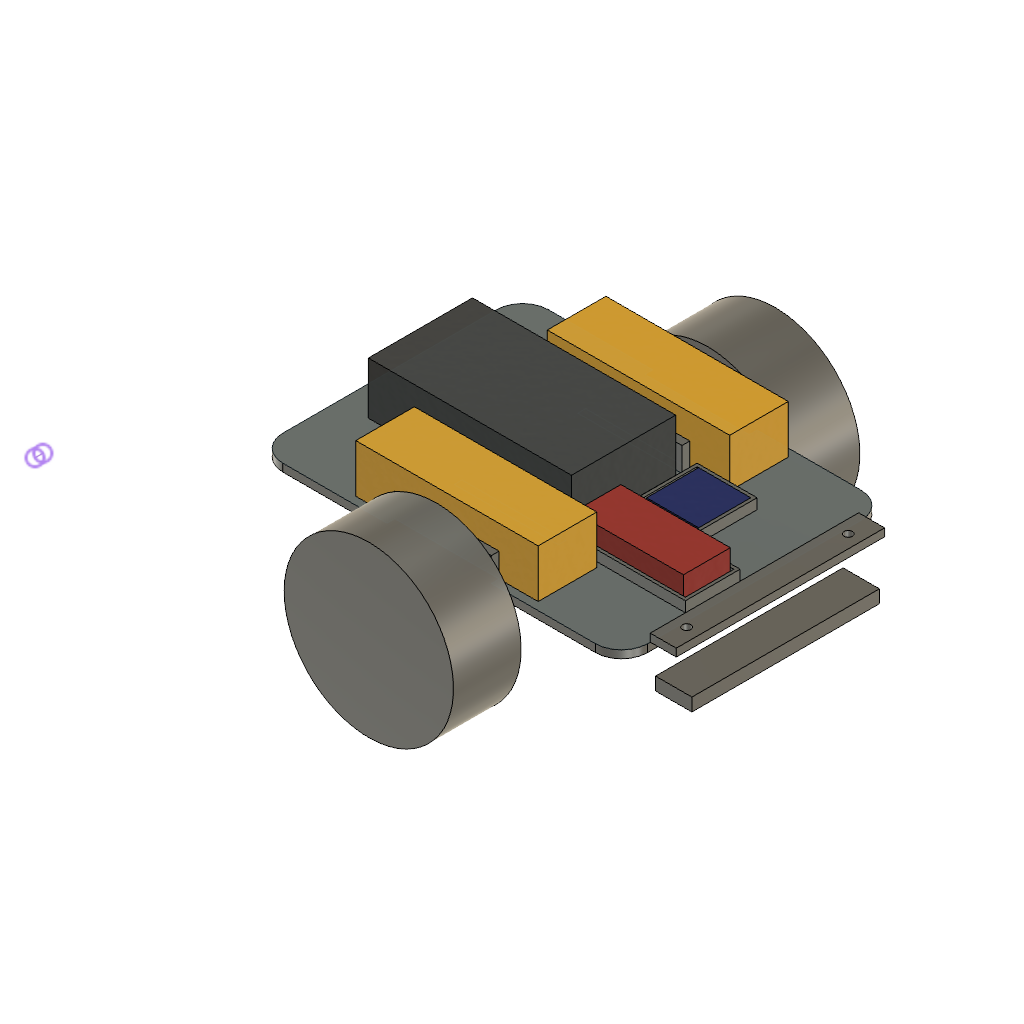
chassis_v1 (Autodesk Fusion 360 design; units mm, degrees)
part number: 2026-11-08-02-27-47-931
part number: 2026-11-08-02-40-19-347
part number: 2026-11-08-02-51-22-051
part number: 2026-11-08-02-55-13-605
part number: 2026-11-08-03-02-01-941
part number: 2026-11-08-03-06-04-735
part number: 2026-11-08-03-13-26-810
part number: 2026-11-08-10-06-36-840
part number: 2026-11-09-11-55-17-820
part number: 2026-11-09-12-28-01-663
Autodesk Fusion 360 part; units mm, degrees
form "Form1" [no effect] in component "DUMMY_Motor"
sketch "sketch 289" plane through (0, 0, 0) normal (0, 0, 1) x (1, 0, 0)
  line L0 (0, 0) -> (70, 0)
  line L1 (70, 0) -> (70, -22.5)
  line L2 (70, -22.5) -> (0, -22.5)
  line L3 (0, -22.5) -> (0, 0)
  constraint horizontal L0
  constraint vertical L1
  constraint horizontal L2
  constraint vertical L3
  constraint coincident L0.start L3.end
extrude "Extrude1" add sketch "sketch 289" along normal blind 18.5 makes body 1 in component "DUMMY_Motor"
form "Form1'" [no effect] in component "DUMMY_Nano"
sketch "sketch 438" plane through (0, 0, 0) normal (0, 0, 1) x (1, 0, 0)
  line L0 (0, 0) -> (42, 0)
  line L1 (42, 0) -> (42, -18)
  line L2 (42, -18) -> (0, -18)
  line L3 (0, -18) -> (0, 0)
  constraint horizontal L0
  constraint vertical L1
  constraint horizontal L2
  constraint vertical L3
  constraint coincident L0.start L3.end
extrude "Extrude1'" add sketch "sketch 438" along normal blind 8 separate body makes body 2 in component "DUMMY_Nano"
form "Form1''" [no effect] in component "DUMMY_Driver"
sketch "sketch 581" plane through (0, 0, 0) normal (0, 0, 1) x (1, 0, 0)
  line L0 (0, 0) -> (20, 0)
  line L1 (20, 0) -> (20, -20)
  line L2 (20, -20) -> (0, -20)
  line L3 (0, -20) -> (0, 0)
  constraint horizontal L0
  constraint vertical L1
  constraint horizontal L2
  constraint vertical L3
  constraint coincident L0.start L3.end
extrude "Extrude1''" add sketch "sketch 581" along normal blind 4 separate body makes body 3 in component "DUMMY_Driver"
move_face "MoveFace1" by (0, -60, 0) 1 faces at (6.6667, -6.6667, 4) on bodies 3 in component "DUMMY_Driver"
sketch "Sketch1" plane through (0, 0, 0) normal (0, 0, 1) x (1, 0, 0) in component "DUMMU_Wheel"
  circle A0 centre (0, 0) radius 32.5
  dimension "d25" = 65
  constraint coincident A0.centre origin
  measures "d25" diameter of A0
extrude "Extrude1'''" add sketch "Sketch1" along normal blind 26 separate body makes body 4 in component "DUMMU_Wheel"
sketch "Sketch1 (2)" plane through (0, 0, 0) normal (0, 0, 1) x (1, 0, 0) in component "Dummy_caster"
  circle A0 centre (0, 0) radius 7.5
  dimension "d28" = 15
  constraint coincident A0.centre origin
  measures "d28" diameter of A0
extrude "Extrude1''''" add sketch "Sketch1 (2)" along normal blind 20.25 separate body makes body 5 in component "Dummy_caster"
sketch "Sketch1 (3)" plane through (0, 0, 0) normal (0, 1, 0) x (1, 0, 0) in component "DUMMY_BATTERY"
sketch "Sketch2" plane through (0, 0, 0) normal (0, 0, 1) x (1, 0, 0) in component "DUMMY_BATTERY"
  line L0 (0, 0) -> (78, 0)
  line L1 (78, 0) -> (78, -40)
  line L2 (78, -40) -> (0, -40)
  line L3 (0, -40) -> (0, 0)
  dimension "d31" = 78
  dimension "d32" = 40
  constraint horizontal L0
  constraint vertical L1
  constraint horizontal L2
  constraint vertical L3
  constraint coincident L0.start L3.end
  measures "d31" distance of L0.start L0.end
  measures "d32" distance of L0.start L2.end
extrude "Extrude1'''''" add sketch "Sketch2" along normal blind 20 separate body makes body 6 in component "DUMMY_BATTERY"
sketch "Sketch1 (4)" plane through (0, 0, 0) normal (0, 0, 1) x (1, 0, 0) in component "Chassis"
  line L0 (0, 0) -> (140, 0)
  line L1 (140, 0) -> (140, 102)
  line L2 (140, 102) -> (0, 102)
  line L3 (0, 102) -> (0, 0)
  dimension "d40" = 140
  dimension "d41" = 102
  constraint horizontal L0
  constraint vertical L1
  constraint horizontal L2
  constraint vertical L3
  constraint coincident L0.start L3.end
  measures "d40" distance of L0.start L0.end
  measures "d41" distance of L0.start L2.end
extrude "Extrude1''''''" add sketch "Sketch1 (4)" along normal blind 3 separate body makes body 7 in component "Chassis"
fillet "Fillet1" radius 10 4 edges at (140, 0, 1.5) (140, 102, 1.5) (0, 102, 1.5) (0, 0, 1.5) on bodies 7 in component "Chassis"
sketch "Sketch2 (2)" plane through (0, 0, 3) normal (0, 0, 1) x (-1, 0, 0) in component "Chassis"
  arc A0 (0, -10) -> (-10, 0) centre (-10, -10) ccw
  line L0 (-10, 0) -> (-130, 0)
  arc A1 (-130, 0) -> (-140, -10) centre (-130, -10) ccw
  line L1 (-140, -10) -> (-140, -92)
  arc A2 (-140, -92) -> (-130, -102) centre (-130, -92) ccw
  line L2 (-130, -102) -> (-10, -102)
  arc A3 (-10, -102) -> (0, -92) centre (-10, -92) ccw
  line L3 (0, -92) -> (0, -10)
  line L4 (-50, 0) -> (-90, 0)
  line L5 (-90, 0) -> (-90, -3)
  line L6 (-90, -3) -> (-50, -3)
  line L7 (-50, -3) -> (-50, 0)
  line L8 (-50, -28.8) -> (-90, -28.8)
  line L9 (-90, -28.8) -> (-90, -25.8)
  line L10 (-90, -25.8) -> (-50, -25.8)
  line L11 (-50, -25.8) -> (-50, -28.8)
  dimension "d53" = 40
  dimension "d54" = 3
  dimension "d55" = 40
  dimension "d56" = 3
  dimension "d57" = 25.8
  dimension "d58" = 50
  dimension "d59" = 50
  constraint horizontal L4
  constraint vertical L5
  constraint horizontal L6
  constraint vertical L7
  constraint coincident L0 L4.start
  constraint horizontal L8
  constraint vertical L9
  constraint horizontal L10
  constraint vertical L11
  measures "d53" distance of L4.start L4.end
  measures "d54" distance of L4.start L6.end
  measures "d55" distance of L8.start L8.end
  measures "d56" distance of L8.start L10.end
  measures "d57" distance of L0 L10
  measures "d58" distance of L3 L11
  measures "d59" distance of L3 L7
sketch "Sketch3" plane through (0, 0, 3) normal (0, 0, 1) x (-1, 0, 0) in component "Chassis"
  line L0 (39.3103, 42.7588) -> (-0.6897, 42.7588)
  line L1 (-0.6897, 42.7588) -> (-0.6897, 45.7588)
  line L2 (-0.6897, 45.7588) -> (39.3103, 45.7588)
  line L3 (39.3103, 45.7588) -> (39.3103, 42.7588)
  dimension "d48" = 40
  dimension "d49" = 3
  constraint horizontal L0
  constraint vertical L1
  constraint horizontal L2
  constraint vertical L3
  measures "d48" distance of L0.start L0.end
  measures "d49" distance of L0.start L2.end
sketch "Sketch4" plane through (0, 0, 3) normal (0, 0, 1) x (-1, 0, 0) in component "Chassis"
  line L0 (-54.873, 44.0948) -> (-94.873, 44.0948)
  line L1 (-94.873, 44.0948) -> (-94.873, 47.0948)
  line L2 (-94.873, 47.0948) -> (-54.873, 47.0948)
  line L3 (-54.873, 47.0948) -> (-54.873, 44.0948)
  dimension "d50" = 40
  dimension "d51" = 3
  constraint horizontal L0
  constraint vertical L1
  constraint horizontal L2
  constraint vertical L3
  measures "d50" distance of L0.start L0.end
  measures "d51" distance of L0.start L2.end
sketch "Sketch5" plane through (0, 0, 3) normal (0, 0, 1) x (-1, 0, 0) in component "Chassis"
sketch "Sketch6" plane through (0, 0, 3) normal (0, 0, 1) x (-1, 0, 0) in component "Chassis"
  line L0 (39.3103, 45.7588) -> (39.3103, 42.7588)
sketch "Sketch7" plane through (0, 0, 3) normal (0, 0, 1) x (1, 0, 0) in component "Chassis"
sketch "Sketch8" plane through (0, 0, 3) normal (0, 0, 1) x (-1, 0, 0) in component "Chassis"
sketch "Sketch9" plane through (0, 0, 3) normal (0, 0, 1) x (-1, 0, 0) in component "Chassis"
sketch "Sketch10" plane through (0, 0, 3) normal (0, 0, 1) x (-1, 0, 0) in component "Chassis"
sketch "Sketch11" plane through (0, 0, 3) normal (0, 0, 1) x (-1, 0, 0) in component "Chassis"
extrude "Extrude2" add sketch "Sketch2 (2)" along normal blind 9.25 contours L0 L4 L5 L6 L7 | L8 L9 L10 L11 bodies 7 in component "Chassis"
ref_plane "WorkPlane1" through (70, 51, 6.125) normal (0, -1, 0) x (1, 0, 0) in component "Chassis"
mirror "Mirror1" about plane through (70, 51, 6.125) normal (0, -1, 0) of "Extrude2" in component "Chassis"
sketch "Sketch12" plane through (0, 0, 3) normal (0, 0, 1) x (-1, 0, 0) in component "Chassis"
  line L0 (-50, -99) -> (-50, -102)
  line L1 (-50, -102) -> (-10, -102)
  arc A0 (-10, -102) -> (0, -92) centre (-10, -92) ccw
  line L2 (0, -92) -> (0, -10)
  arc A1 (0, -10) -> (-10, 0) centre (-10, -10) ccw
  line L3 (-10, 0) -> (-50, 0)
  line L4 (-50, 0) -> (-50, -3)
  line L5 (-50, -3) -> (-90, -3)
  line L6 (-90, -3) -> (-90, 0)
  line L7 (-90, 0) -> (-130, 0)
  arc A2 (-130, 0) -> (-140, -10) centre (-130, -10) ccw
  line L8 (-140, -10) -> (-140, -92)
  arc A3 (-140, -92) -> (-130, -102) centre (-130, -92) ccw
  line L9 (-130, -102) -> (-90, -102)
  line L10 (-90, -102) -> (-90, -99)
  line L11 (-90, -99) -> (-50, -99)
  line L12 (-50, -73.2) -> (-50, -76.2)
  line L13 (-50, -76.2) -> (-90, -76.2)
  line L14 (-90, -76.2) -> (-90, -73.2)
  line L15 (-90, -73.2) -> (-50, -73.2)
  line L16 (-50, -25.8) -> (-50, -28.8)
  line L17 (-50, -28.8) -> (-90, -28.8)
  line L18 (-90, -28.8) -> (-90, -25.8)
  line L19 (-90, -25.8) -> (-50, -25.8)
mirror "Mirror1'" about plane through (35, 25.5, 3.875) normal (0, -1, 0) of "Extrude1" makes body 8 in component "DUMMY_Motor"
sketch "Sketch13" plane through (0, 0, 3) normal (0, 0, 1) x (-1, 0, 0) in component "Chassis"
  line L0 (-140, -91) -> (-150, -91)
  line L1 (-150, -91) -> (-150, -11)
  line L2 (-150, -11) -> (-140, -11)
  line L3 (-140, -11) -> (-140, -91)
  line L4 (0, -92) -> (0, -10)
  dimension "d78" = 140
  dimension "d79" = 10
  dimension "d80" = 80
  constraint horizontal L0
  constraint vertical L1
  constraint horizontal L2
  constraint vertical L3
  measures "d78" distance of L3 L4
  measures "d79" distance of L1 L3
  measures "d80" distance of L0 L2
sketch "Sketch14" plane through (0, 0, 3) normal (0, 0, 1) x (-1, 0, 0) in component "Chassis"
extrude "Extrude3" add sketch "Sketch13" along normal blind 3 separate body makes body 9 in component "Chassis"
combine "Combine1" operation add target body 7 tool bodies 9 in component "Chassis"
sketch "Sketch15" plane through (0, 0, 3) normal (0, 0, 1) x (-1, 0, 0) in component "Chassis"
  line L0 (-50, -99) -> (-50, -102)
  line L1 (-50, -102) -> (-10, -102)
  arc A0 (-10, -102) -> (0, -92) centre (-10, -92) ccw
  line L2 (0, -92) -> (0, -10)
  arc A1 (0, -10) -> (-10, 0) centre (-10, -10) ccw
  line L3 (-10, 0) -> (-50, 0)
  line L4 (-50, 0) -> (-50, -3)
  line L5 (-50, -3) -> (-90, -3)
  line L6 (-90, -3) -> (-90, 0)
  line L7 (-90, 0) -> (-130, 0)
  arc A2 (-130, 0) -> (-140, -10) centre (-130, -10) ccw
  line L8 (-140, -10) -> (-140, -11)
  line L9 (-140, -11) -> (-140, -91)
  line L10 (-140, -91) -> (-140, -92)
  arc A3 (-140, -92) -> (-130, -102) centre (-130, -92) ccw
  line L11 (-130, -102) -> (-90, -102)
  line L12 (-90, -102) -> (-90, -99)
  line L13 (-90, -99) -> (-50, -99)
  line L14 (-50, -73.2) -> (-50, -76.2)
  line L15 (-50, -76.2) -> (-90, -76.2)
  line L16 (-90, -76.2) -> (-90, -73.2)
  line L17 (-90, -73.2) -> (-50, -73.2)
  line L18 (-50, -25.8) -> (-50, -28.8)
  line L19 (-50, -28.8) -> (-90, -28.8)
  line L20 (-90, -28.8) -> (-90, -25.8)
  line L21 (-90, -25.8) -> (-50, -25.8)
  circle A4 centre (-145, -20) radius 1.6
  circle A5 centre (-145, -82) radius 1.6
  dimension "d83" = 3.2
  dimension "d84" = 3.2
  dimension "d85" = 20
  dimension "d86" = 82
  measures "d83" diameter of A4
  measures "d84" diameter of A5
  measures "d85" distance of L7 A4.centre
  measures "d86" distance of L7 A5.centre
extrude "Extrude4" cut sketch "Sketch15" along normal blind 3 contours A4 | A5 bodies 7 in component "Chassis"
sketch "Sketch16" plane through (0, 0, 3) normal (0, 0, 1) x (-1, 0, 0) in component "Chassis"
  circle A0 centre (-7, -61) radius 1.6
  circle A1 centre (-7, -41) radius 1.6
  line L0 (0, -92) -> (0, -10)
  line L1 (-10, 0) -> (-50, 0)
  dimension "d89" = 3.2
  dimension "d90" = 3.2
  dimension "d91" = 7
  dimension "d92" = 7
  dimension "d93" = 41
  dimension "d94" = 61
  measures "d89" diameter of A0
  measures "d90" diameter of A1
  measures "d91" distance of A1.centre L0
  measures "d92" distance of A0.centre L0
  measures "d93" distance of A1.centre L1
  measures "d94" distance of A0.centre L1
extrude "Extrude5" cut sketch "Sketch16" against normal blind 3 bodies 7 in component "Chassis"
sketch "Sketch17" plane through (0, 0, 3) normal (0, 0, 1) x (-1, 0, 0) in component "Chassis"
  line L0 (-92.2, -47.3) -> (-135.8, -47.3)
  line L1 (-135.8, -47.3) -> (-135.8, -28.7)
  line L2 (-135.8, -28.7) -> (-92.2, -28.7)
  line L3 (-92.2, -28.7) -> (-92.2, -47.3)
  line L4 (0, -92) -> (0, -10)
  line L5 (-90, 0) -> (-130, 0)
  line L6 (-137, -27.5) -> (-91, -27.5)
  line L7 (-91, -27.5) -> (-91, -48.5)
  line L8 (-91, -48.5) -> (-137, -48.5)
  line L9 (-137, -48.5) -> (-137, -27.5)
  dimension "d97" = 43.6
  dimension "d98" = 18.6
  dimension "d99" = 92.2
  dimension "d100" = 28.7
  constraint horizontal L0
  constraint vertical L1
  constraint horizontal L2
  constraint vertical L3
  measures "d97" distance of L0.start L0.end
  measures "d98" distance of L0.start L2.end
  measures "d99" distance of L3 L4
  measures "d100" distance of L2 L5
sketch "Sketch18" plane through (0, 0, 3) normal (0, 0, 1) x (-1, 0, 0) in component "Chassis"
  line L0 (-94.7, -74.3) -> (-115.3, -74.3)
  line L1 (-115.3, -74.3) -> (-115.3, -53.7)
  line L2 (-115.3, -53.7) -> (-94.7, -53.7)
  line L3 (-94.7, -53.7) -> (-94.7, -74.3)
  line L4 (0, -92) -> (0, -10)
  line L5 (-90, 0) -> (-130, 0)
  line L6 (-116.5, -52.5) -> (-93.5, -52.5)
  line L7 (-93.5, -52.5) -> (-93.5, -75.5)
  line L8 (-93.5, -75.5) -> (-116.5, -75.5)
  line L9 (-116.5, -75.5) -> (-116.5, -52.5)
  dimension "d102" = 20.6
  dimension "d103" = 20.6
  dimension "d104" = 94.7
  dimension "d105" = 53.7
  constraint horizontal L0
  constraint vertical L1
  constraint horizontal L2
  constraint vertical L3
  measures "d102" distance of L0.start L0.end
  measures "d103" distance of L0.start L2.end
  measures "d104" distance of L3 L4
  measures "d105" distance of L2 L5
extrude "Extrude6" add sketch "Sketch17" sketch "Sketch18" along normal blind 4 separate body of sketch 2 makes body 10 at (121.6667, 27.5, 4.3333) makes body 11 at (108.4333, 52.9, 3) in component "Chassis"
sketch "Sketch19" plane through (0, 0, 3) normal (0, 0, 1) x (-1, 0, 0) in component "Chassis"
  line L0 (-19, -30.5) -> (-31, -30.5)
  line L1 (-31, -30.5) -> (-31, -27.5)
  line L2 (-31, -27.5) -> (-19, -27.5)
  line L3 (-19, -27.5) -> (-19, -30.5)
  line L4 (0, -92) -> (0, -10)
  line L5 (-10, 0) -> (-50, 0)
  line L6 (-19, -74.5) -> (-31, -74.5)
  line L7 (-31, -74.5) -> (-31, -71.5)
  line L8 (-31, -71.5) -> (-19, -71.5)
  line L9 (-19, -71.5) -> (-19, -74.5)
  line L10 (-35, -30.5) -> (-47, -30.5)
  line L11 (-47, -30.5) -> (-47, -27.5)
  line L12 (-47, -27.5) -> (-35, -27.5)
  line L13 (-35, -27.5) -> (-35, -30.5)
  line L14 (-35, -74.5) -> (-47, -74.5)
  line L15 (-47, -74.5) -> (-47, -71.5)
  line L16 (-47, -71.5) -> (-35, -71.5)
  line L17 (-35, -71.5) -> (-35, -74.5)
  dimension "d109" = 12
  dimension "d110" = 3
  dimension "d111" = 19
  dimension "d112" = 27.5
  dimension "d113" = 12
  dimension "d114" = 3
  dimension "d115" = 12
  dimension "d116" = 3
  dimension "d117" = 35
  dimension "d118" = 19
  dimension "d119" = 27.5
  dimension "d120" = 71.5
  dimension "d121" = 12
  dimension "d122" = 3
  dimension "d123" = 35
  dimension "d124" = 71.5
  constraint horizontal L0
  constraint vertical L1
  constraint horizontal L2
  constraint vertical L3
  constraint horizontal L6
  constraint vertical L7
  constraint horizontal L8
  constraint vertical L9
  constraint horizontal L10
  constraint vertical L11
  constraint horizontal L12
  constraint vertical L13
  constraint horizontal L14
  constraint vertical L15
  constraint horizontal L16
  constraint vertical L17
  measures "d109" distance of L0.start L0.end
  measures "d110" distance of L0.start L2.end
  measures "d111" distance of L3 L4
  measures "d112" distance of L2 L5
  measures "d113" distance of L6.start L6.end
  measures "d114" distance of L6.start L8.end
  measures "d115" distance of L10.start L10.end
  measures "d116" distance of L10.start L12.end
  measures "d117" distance of L4 L13
  measures "d118" distance of L4 L9
  measures "d119" distance of L5 L12
  measures "d120" distance of L5 L8
  measures "d121" distance of L14.start L14.end
  measures "d122" distance of L14.start L16.end
  measures "d123" distance of L4 L17
  measures "d124" distance of L5 L16
extrude "Extrude7" cut sketch "Sketch19" against normal blind 3 bodies 7 in component "Chassis"
sketch "Sketch1 (5)" plane through (0, 0, 0) normal (0, 1, 0) x (1, 0, 0) in component "Dummy_Wheel"
sketch "Sketch2 (3)" plane through (0, 0, 0) normal (0, 1, 0) x (1, 0, 0) in component "Dummy_Wheel"
  circle A0 centre (70, 12.25) radius 32.5
  line L0 (0, -1.75) -> (0, -22.5)
  line L1 (10, 0) -> (130, 0)
  dimension "d130" = 65
  dimension "d131" = 70
  dimension "d132" = 12.25
  measures "d130" diameter of A0
  measures "d131" distance of A0.centre L0
  measures "d132" distance of A0.centre L1
extrude "Extrude1'''''''" add sketch "Sketch2 (3)" against normal blind 26 separate body makes body 12 in component "Dummy_Wheel"
mirror "Mirror1''" about plane through (70, 52, 6.125) normal (0, -1, 0) of "Extrude1'''''''" makes body 13 in component "Dummy_Wheel"
move_face "MoveFace1'" by (0, 0, 2) 1 faces at (14, -6, 8) on bodies 2 in component "DUMMY_Nano"
ref_plane "WorkPlane1" through (0, 0, -16.25) normal (0, 0, 1) x (1, 0, 0) in component "DUMMY_SensorBar"
sketch "Sketch1 (6)" plane through (0, 0, -16.25) normal (0, 0, 1) x (1, 0, 0) in component "DUMMY_SensorBar"
  line L0 (138, 87) -> (152, 87)
  line L1 (152, 87) -> (152, 15)
  line L2 (152, 15) -> (138, 15)
  line L3 (138, 15) -> (138, 87)
  line L4 (0, 92) -> (0, 10)
  line L5 (90, 0) -> (130, 0)
  dimension "d139" = 14
  dimension "d140" = 72
  dimension "d141" = 138
  dimension "d142" = 15
  constraint horizontal L0
  constraint vertical L1
  constraint horizontal L2
  constraint vertical L3
  measures "d139" distance of L0.start L0.end
  measures "d140" distance of L0.start L2.end
  measures "d141" distance of L3 L4
  measures "d142" distance of L2 L5
extrude "Extrude1''''''''" add sketch "Sketch1 (6)" along normal blind 5 separate body makes body 14 in component "DUMMY_SensorBar"
component "DUMMY_Nano" placed x (1, 0, 0) y (0, 1, 0) z (0, 0, 1) at (92, 47.5, 4)
component "DUMMY_Driver" placed x (1, 0, 0) y (0, 1, 0) z (0, 0, 1) at (95.3, 74.3, 3)
component "DUMMY_Motor" placed x (1, 0, 0) y (0, 1, 0) z (0, 0, 1) at (35, 25.5, 2.25)
component "DUMMY_BATTERY" placed x (1, 0, 0) y (0, 1, 0) z (0, 0, 1) at (11.4303, 71.3606, 0)
component "Chassis" placed x (1, 0, 0) y (0, 1, 0) z (0, 0, 1) at (0, 0, 0)
component "Dummy_Wheel" placed x (1, 0, 0) y (0, 1, 0) z (0, 0, 1) at (0, -1, 0)
component "DUMMY_SensorBar" placed x (1, 0, 0) y (0, 1, 0) z (0, 0, 1) at (0, 0, 0)
equation "motor_l = 70 mm" comment "TT motor length"
equation "motor_w = 22.5 mm"
equation "motor_h = 18.5 mm"
equation "wheel_d = 65 mm"
equation "wheel_w = 26 mm"
equation "wheel_gap = 1 mm"
equation "plate_t = 3 mm"
equation "plate_w = 102 mm"
equation "plate_l = 140 mm"
equation "corner_r = 10 mm"
equation "tol = 0.3 mm"
equation "clearance = wheel_d / 2 - motor_h / 2 - plate_t"
equation "axle_y = 15 mm"
equation "caster_y = -55 mm"
equation "sensor_ahead = 75 mm"
equation "d16 = motor_h"
equation "d25 = wheel_d"
equation "d26 = wheel_w"
equation "d29 = clearance"
equation "rail_t = 3 mm"
equation "rail_l = 40 mm"
equation "rail_h = motor_h / 2"
equation "motor_x = plate_w / 2 - rail_t - ( motor_w + tol ) / 2"
equation "d40 = plate_l"
equation "d41 = plate_w"
equation "d42 = plate_t"
equation "d45 = corner_r"
equation "rail_gap = motor_w + tol"
equation "rail_start = ( plate_l - rail_l ) / 2"
equation "d48 = rail_l"
equation "d49 = rail_t"
equation "d50 = rail_l"
equation "d51 = rail_t"
equation "d53 = rail_l"
equation "d54 = rail_t"
equation "d55 = rail_l"
equation "d56 = rail_t"
equation "d57 = rail_t + rail_gap"
equation "d58 = rail_start"
equation "d59 = rail_start"
equation "d60 = rail_h"
equation "hole_d = 3.2 mm"
equation "shelf_d = 10 mm"
equation "shelf_w = 80 mm"
equation "caster_x = 7 mm"
equation "caster_s = 20 mm"
equation "rim_t = 1.2 mm"
equation "rim_h = 4 mm"
equation "nano_l = 43.6 mm"
equation "nano_w = 18.6 mm"
equation "drv_s = 20.6 mm"
equation "strap_l = 12 mm"
equation "strap_t = 3 mm"
equation "d78 = plate_l"
equation "d79 = shelf_d"
equation "d80 = shelf_w"
equation "d81 = plate_t"
equation "d83 = hole_d"
equation "d84 = hole_d"
equation "d85 = plate_w / 2 - 31 mm"
equation "d86 = plate_w / 2 + 31 mm"
equation "d87 = plate_t"
equation "d89 = hole_d"
equation "d90 = hole_d"
equation "d91 = caster_x"
equation "d92 = caster_x"
equation "d93 = plate_w / 2 - caster_s / 2"
equation "d94 = plate_w / 2 + caster_s / 2"
equation "d95 = -plate_t"
equation "d97 = nano_l"
equation "d98 = nano_w"
equation "d99 = 114 mm - nano_l / 2"
equation "d100 = 38 mm - nano_w / 2"
equation "d101 = -rim_t"
equation "d102 = drv_s"
equation "d103 = drv_s"
equation "d104 = 105 mm - drv_s / 2"
equation "d105 = 64 mm - drv_s / 2"
equation "d106 = -rim_t"
equation "d107 = rim_h"
equation "d109 = strap_l"
equation "d110 = strap_t"
equation "d111 = 25 mm - strap_l / 2"
equation "d112 = 29 mm - strap_t / 2"
equation "d113 = strap_l"
equation "d114 = strap_t"
equation "d115 = strap_l"
equation "d116 = strap_t"
equation "d121 = strap_l"
equation "d122 = strap_t"
equation "axle_x = 70 mm"
equation "axle_z = plate_t + motor_h / 2"
equation "sensor_h = 4 mm"
equation "d130 = wheel_d"
equation "d131 = axle_x"
equation "d132 = axle_z"
equation "d133 = -wheel_w"
equation "d137 = -( clearance - sensor_h )"
equation "d141 = plate_l + shelf_d / 2 - 7 mm"
equation "d142 = plate_w / 2 - 36 mm"
named bodies: "motor_body", "motor_body (1)"
